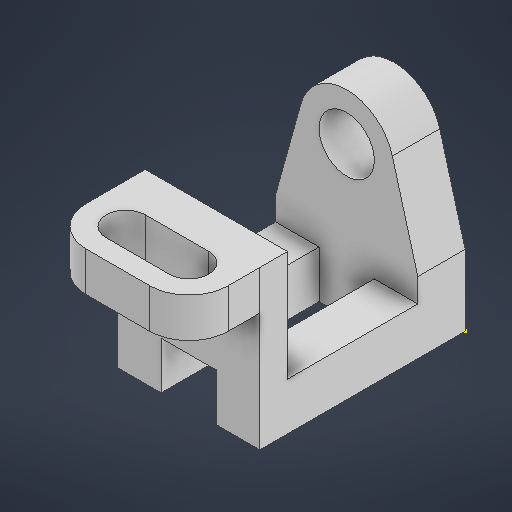
# Autodesk Inventor part: Peça2
Saved by Autodesk Inventor 2026.2 (Build 302298000, 298)
## iProperties
Created: 2026-07-31
Part Number: Peça2
Material: Genérico
Document SubType Name: Modeling
Designer: IFSP
Density: 1 g/cm^3
Appearance: Padrão
Author: IFSP
Autodesk Inventor part; units mm, degrees
ref_plane "YZ Plane" through (0, 0, 0) normal (1, 0, 0) x (0, 1, 0)
ref_plane "XZ Plane" through (0, 0, 0) normal (0, 1, 0) x (-1, 0, 0)
ref_plane "XY Plane" through (0, 0, 0) normal (0, 0, 1) x (1, 0, 0)
sketch "Esboço1" plane through (0, 0, 0) normal (0, 0, 1) x (1, 0, 0)
  line L0 (0, 0) -> (36, 0)
  line L1 (36, 0) -> (36, 18)
  line L2 (0, 0) -> (0, 18)
  line L3 (18, 0) -> (18, 38)
  circle A0 centre (18, 38) radius 12
  circle A1 centre (18, 38) radius 7
  line L4 (0, 18) -> (6.4365, 41.2071)
  line L5 (36, 18) -> (29.5635, 41.2071)
  dimension "d0" = 36
  dimension "d1" = 18
  dimension "d2" = 18
  dimension "d3" = 38
  dimension "d4" = 24
  dimension "d5" = 14
  constraints: 12 end point, 2 centre point, 2 coincident, 2 point on circle, 2 tangent, 2 vertical, 1 horizontal, 1 midpoint, 1 perpendicular
  measures "d0" distance of L0.start L0.end
  measures "d1" distance of L0.end L1.end
  measures "d2" distance of L0.start L2.end
  measures "d3" distance of L3.start L3.end
  measures "d4" diameter of A0
  measures "d5" diameter of A1
extrude "Extrusão1" add sketch "Esboço1" along normal blind 12
sketch "Esboço2" plane through (36, 0, 0) normal (1, 0, 0) x (0, 0, -1)
  line L0 (-12, 18) -> (-12, 0) projected
  line L1 (-12, 0) -> (-52, 0)
  line L2 (-12, 0) -> (-12, 12)
  line L3 (-12, 12) -> (-52, 12)
  line L4 (-52, 12) -> (-52, 0)
  point P0 (0, 0)
  dimension "d8" = 40
  dimension "d9" = 12
  dimension "d10" = 40
  constraints: 8 end point, 1 horizontal, 1 perpendicular, 1 point on line
  measures "d8" distance of L0.end L1.end
  measures "d9" distance of L0.end L2.end
  measures "d10" distance of L2.end L3.end
extrude "Extrusão2" add sketch "Esboço2" against normal blind 11
sketch "Esboço3" plane through (36, 0, 0) normal (1, 0, 0) x (0, 0, -1)
  point P0 (0, 0)
sketch "Esboço4" plane through (36, 0, 52) normal (0, 0, 1) x (1, 0, 0)
  line L0 (-36, 0) -> (0, 0) projected
  line L1 (0, 0) -> (-11, 0)
  line L2 (-36, 0) -> (-25, 0)
  line L3 (-25, 0) -> (-25, 12)
  line L4 (-25, 12) -> (-36, 12)
  line L5 (-36, 12) -> (-36, 0)
  dimension "d13" = 11
  dimension "d14" = 11
  dimension "d15" = 12
  constraints: 10 end point, 3 perpendicular, 2 point on line
  measures "d13" distance of L0.end L1.end
  measures "d14" distance of L0.start L2.end
  measures "d15" distance of L2.end L3.end
extrude "Extrusão3" add sketch "Esboço4" against normal blind 40
sketch "Esboço5" plane through (36, 0, 0) normal (1, 0, 0) x (0, 0, -1)
  line L0 (0, 0) -> (-52, 0) projected
  line L1 (-52, 0) -> (-45, 0)
  line L2 (-45, 0) -> (-45, 40)
  line L3 (-45, 40) -> (-52, 40)
  line L4 (-52, 40) -> (-52, 0)
  line L5 (-52, 12) -> (-12, 12) projected
  line L6 (-45, 12) -> (-52, 12)
  dimension "d18" = 7
  dimension "d19" = 40
  constraints: 10 end point, 3 perpendicular, 3 point on line, 1 collinear
  measures "d18" distance of L0.end L1.end
  measures "d19" distance of L1.end L2.end
extrude "Extrusão4" add sketch "Esboço5" against normal blind 36 contours L5 L4 L3 L2
sketch "Esboço6" plane through (36, 40, 52) normal (0, 1, 0) x (1, 0, 0)
  line L0 (-36, 52) -> (-36, 0) projected
  line L1 (-36, 7.0626) -> (-36, -7.9374)
  line L2 (-11, 7) -> (0, 7) projected
  line L3 (-0.0016, -7.9385) -> (0, 7)
  line L4 (-36, -7.9374) -> (-36, -8.1642)
  line L5 (-26.2268, -17.9374) -> (-10, -17.9374)
  circle A0 centre (-26, -7.9374) radius 5
  arc A1 (-36, -7.7106) -> (-25.9984, -17.94) centre (-26, -7.9374) ccw
  circle A2 centre (-10.0016, -7.9374) radius 5
  arc A3 (-10, -17.9374) -> (-0.0016, -7.9385) centre (-10.0016, -7.9374) ccw
  line L6 (-25.9984, -17.94) -> (-10, -17.9374)
  line L7 (0, 7) -> (-36, 7) projected
  line L8 (-36, 7) -> (0, 7)
  line L9 (0, 7) -> (-0.0016, -7.9385)
  line L10 (0, 7) -> (-0.0016, -7.9385)
  line L11 (-36, 7) -> (-36, -7.7106)
  circle A4 centre (-26, -7.9374) radius 10.0026
  circle A5 centre (-10.0016, -7.9374) radius 10
  line L12 (-25.9984, -17.94) -> (-10, -17.9374)
  line L13 (-36, 0) -> (-25, 0) projected
  line L14 (-36, 0) -> (-0.0008, 0)
  point P0 (-0.0008, 0)
  constraints: 22 end point, 7 collinear, 6 centre point, 6 point on circle, 4 coincident, 4 tangent, 3 point on line, 2 concentric, 1 perpendicular, 1 vertical
extrude "Extrusão5" add sketch "Esboço6" against normal blind 10 contours L13 A4 L1 | A4 L13 L14 A5 L5 A1 L4 L1 | L14 A5 A4 | L3 A5 L14 | A5 L14 A3 A4 | A4 A5 | A4 A5 L5
sketch "Esboço7" plane through (36, 40, 52) normal (0, 1, 0) x (1, 0, 0)
  circle A0 centre (-26, -7.9374) radius 5 projected
  circle A1 centre (-10.0016, -7.9374) radius 5 projected
  line L0 (-26, -2.9374) -> (-10.0016, -2.9374)
  line L1 (-10.0016, -2.9374) -> (-10.0016, -12.9374)
  line L2 (-10.0016, -12.9374) -> (-26, -12.9374)
  line L3 (-26, -12.9374) -> (-26, -2.9374)
  point P0 (-36, 52)
  point P1 (-10.0016, -2.9374)
  constraints: 8 end point, 2 parallel, 1 horizontal, 1 perpendicular, 4 other
extrude "Extrusão6" cut sketch "Esboço7" against normal blind 10 contours A0 L0 A1 L2
